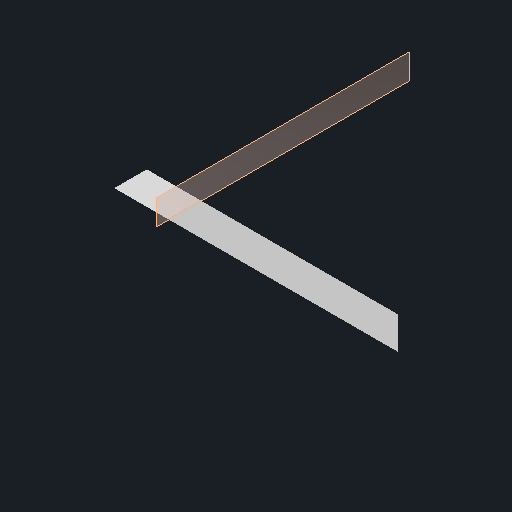
# Autodesk Inventor part: Top of Diagonals 1
Saved by Autodesk Inventor 2027 (Build 310192000, 192)
## iProperties
Created: 2026-10-17
Part Number: Top of Diagonals 1
Material: Generic
Document SubType Name: Modeling
Designer: lucas
Density: 1 g/cm^3
Appearance: Default
Author: lucas
Autodesk Inventor part; units mm, degrees
ref_plane "YZ Plane" through (0, 0, 0) normal (1, 0, 0) x (0, 1, 0)
ref_plane "XZ Plane" through (0, 0, 0) normal (0, 1, 0) x (-1, 0, 0)
ref_plane "XY Plane" through (0, 0, 0) normal (0, 0, 1) x (1, 0, 0)
ref_plane "Work Plane1" through (647.7, 336.55, 381) normal (1, 0, 0) x (0, 0, -1)
sketch "Sketch1" plane through (647.7, 336.55, 381) normal (1, 0, 0) x (0, 0, -1)
  line L0 (381, -381) -> (0, 0)
  line L1 (319.6338, -265.7523) -> (53.8815, 0)
  line L2 (53.8815, 0) -> (0, 0)
  line L3 (319.6338, -265.7523) -> (381, -327.1185)
  line L4 (381, -327.1185) -> (381, -381)
  point P0 (381, -336.55)
  dimension "d0" = 38.1
  constraints: 10 end point, 1 horizontal, 1 parallel, 1 vertical, 2 other
  measures "d0" distance between parallel lines of L0 L1
extrude "Extrusion1" add sketch "Sketch1" against normal blind 88.9
body "Solid1"
